new-gripper (Autodesk Fusion 360 design; units mm, degrees)
Autodesk Fusion 360 part; units mm, degrees
sketch "스케치1" plane through (0, 0, 0) normal (0, 0, 1) x (1, 0, 0)
  line L0 (0, 0) -> (40, 0)
  line L1 (40, 0) -> (40, 100)
  line L2 (40, 100) -> (0, 100)
  line L3 (0, 100) -> (0, 0)
  line L4 (50, 0) -> (90, 0)
  line L5 (90, 0) -> (90, 100)
  line L6 (90, 100) -> (50, 100)
  line L7 (50, 100) -> (50, 0)
  dimension "d1" = 40
  dimension "d2" = 100
  dimension "d3" = 40
  dimension "d4" = 100
  constraint horizontal L0
  constraint vertical L1
  constraint horizontal L2
  constraint vertical L3
  constraint coincident L0.start L3.end
  constraint horizontal L4
  constraint vertical L5
  constraint horizontal L6
  constraint vertical L7
  measures "d1" distance of L0.start L0.end
  measures "d2" distance of L0.start L2.end
  measures "d3" distance of L4.start L4.end
  measures "d4" distance of L4.start L6.end
extrude "돌출1" add sketch "스케치1" along normal blind 1.5 contours L0 L1 L2 L3 makes body 1 in component "Component"
extrude "돌출1'" add sketch "스케치1" along normal blind 1.5 separate body contours L4 L5 L6 L7 makes body 2 in component "Component'"
extrude "돌출2" add 1 faces at (90, 33.3333, 0.5) along direction (1, 0, 0) blind 3 on bodies 2 bodies 2 in component "Component'"
extrude "돌출2'" add 1 faces at (0, 66.6667, 0.5) along direction (-1, 0, 0) blind 3 on bodies 1 bodies 1 in component "Component"
sketch "스케치2" plane through (0, 0, 1.5) normal (0, 0, 1) x (-1, 0, 0)
  line L0 (-50, -100) -> (-50, 0)
  line L1 (-50, 0) -> (-93, 0)
  line L2 (-93, 0) -> (-93, -100)
  line L3 (-93, -100) -> (-50, -100)
  line L4 (-93, 0) -> (-90, 0)
  line L5 (-90, 0) -> (-90, -100)
  line L6 (-90, -100) -> (-93, -100)
  line L7 (-93, -100) -> (-93, 0)
  dimension "d13" = 3
  constraint horizontal L4
  constraint vertical L5
  constraint horizontal L6
  constraint vertical L7
  constraint coincident L3 L5.end
  constraint coincident L1.end L2.start
  measures "d13" distance of L1.end L4.end
extrude "돌출1''" add sketch "스케치2" along normal blind 80 separate body contours L1 L2 L3 L4 L5 L6 L7 makes body 3 in component "Component''"
sketch "스케치3" plane through (0, 0, 1.5) normal (0, 0, 1) x (-1, 0, 0)
  line L0 (3, 0) -> (-40, 0)
  line L1 (-40, 0) -> (-40, -100)
  line L2 (-40, -100) -> (3, -100)
  line L3 (3, -100) -> (3, 0)
  line L4 (3, 0) -> (0, 0)
  line L5 (0, 0) -> (0, -100)
  line L6 (0, -100) -> (3, -100)
  line L7 (3, -100) -> (3, 0)
  dimension "d16" = 3
  dimension "d17" = 100
  constraint horizontal L4
  constraint vertical L5
  constraint horizontal L6
  constraint vertical L7
  constraint coincident L0.start L3.end
  measures "d16" distance of L0.start L4.end
  measures "d17" distance of L0.start L2.end
extrude "돌출1'''" add sketch "스케치3" along normal blind 80 separate body contours L0 L2 L3 L4 L5 L6 L7 makes body 4 in component "Component'''"
sketch "스케치4" plane through (0, 0, 81.5) normal (0, 0, 1) x (-1, 0, 0)
  line L0 (3, -100) -> (3, 0)
  line L1 (3, 0) -> (0, 0)
  line L2 (0, 0) -> (0, -100)
  line L3 (0, -100) -> (3, -100)
  line L4 (3, -100) -> (-40, -100)
  line L5 (-40, -100) -> (-40, 0)
  line L6 (-40, 0) -> (3, 0)
  line L7 (3, 0) -> (3, -100)
  dimension "d20" = 43
  dimension "d21" = 100
  constraint horizontal L4
  constraint vertical L5
  constraint horizontal L6
  constraint vertical L7
  constraint coincident L0.start L3.end
  measures "d20" distance of L0.start L4.end
  measures "d21" distance of L0.start L0.end
extrude "돌출1''''" add sketch "스케치4" along normal blind 3 separate body makes body 5 in component "Component''''"
sketch "스케치5" plane through (0, 0, 81.5) normal (0, 0, 1) x (-1, 0, 0)
  line L0 (-93, -100) -> (-90, -100)
  line L1 (-90, -100) -> (-90, 0)
  line L2 (-90, 0) -> (-93, 0)
  line L3 (-93, 0) -> (-93, -100)
  line L4 (-93, -100) -> (-50, -100)
  line L5 (-50, -100) -> (-50, 0)
  line L6 (-50, 0) -> (-93, 0)
  line L7 (-93, 0) -> (-93, -100)
  dimension "d24" = 43
  dimension "d25" = 100
  constraint horizontal L4
  constraint vertical L5
  constraint horizontal L6
  constraint vertical L7
  constraint coincident L0.start L3.end
  measures "d24" distance of L0.start L4.end
  measures "d25" distance of L0.start L2.end
extrude "돌출1'''''" add sketch "스케치5" along normal blind 3 separate body makes body 6 in component "Component'''''"
sketch "스케치6" plane through (0, 0, 84.5) normal (0, 0, 1) x (-1, 0, 0)
  line L0 (-93, 0) -> (-93, -100)
  line L1 (-93, -100) -> (-50, -100)
  line L2 (-50, -100) -> (-50, 0)
  line L3 (-50, 0) -> (-93, 0)
  circle A0 centre (-85, -50) radius 1.5
  dimension "d28" = 3
  dimension "d29" = 35
  dimension "d30" = 50
  measures "d28" diameter of A0
  measures "d29" distance of L2 A0.centre
  measures "d30" distance of L3 A0.centre
sketch "스케치7" plane through (0, 0, 84.5) normal (0, 0, 1) x (-1, 0, 0)
  line L0 (3, 0) -> (-40, 0)
  line L1 (-40, 0) -> (-40, -100)
  line L2 (-40, -100) -> (3, -100)
  line L3 (3, -100) -> (3, 0)
  circle A0 centre (-5, -50) radius 1.5
  dimension "d31" = 3
  dimension "d32" = 35
  measures "d31" diameter of A0
  measures "d32" distance of L1 A0.centre
extrude "돌출2''" cut sketch "스케치7" sketch "스케치6" against normal blind 4 contours A0 of sketch 2 contours A0 bodies 5 in component "Component''''"
extrude "돌출2'''" cut sketch "스케치7" sketch "스케치6" against normal blind 4 contours A0 of sketch 2 contours A0 bodies 6 in component "Component'''''"
sketch "스케치8" plane through (0, 0, 84.5) normal (0, 0, 1) x (-1, 0, 0)
  circle A0 centre (-85, -50) radius 1.5
  line L0 (-93, 0) -> (-93, -100)
  line L1 (-93, -100) -> (-50, -100)
  line L2 (-50, -100) -> (-50, 0)
  line L3 (-50, 0) -> (-93, 0)
  line L4 (-90, -45) -> (-55, -45)
  line L5 (-55, -45) -> (-55, -55)
  line L6 (-55, -55) -> (-90, -55)
  line L7 (-90, -55) -> (-90, -45)
  dimension "d37" = 35
  dimension "d38" = 10
  constraint horizontal L4
  constraint vertical L5
  constraint horizontal L6
  constraint vertical L7
  measures "d37" distance of L4.start L4.end
  measures "d38" distance of L4.start L6.end
extrude "돌출1''''''" add sketch "스케치8" along normal blind 3 separate body contours L4 L5 L6 L7 makes body 7 in component "Component''''''"
sketch "스케치9" plane through (0, 0, 84.5) normal (0, 0, 1) x (-1, 0, 0)
  circle A0 centre (-5, -50) radius 1.5
  line L0 (3, 0) -> (-40, 0)
  line L1 (-40, 0) -> (-40, -100)
  line L2 (-40, -100) -> (3, -100)
  line L3 (3, -100) -> (3, 0)
  line L4 (0, -55) -> (-35, -55)
  line L5 (-35, -55) -> (-35, -45)
  line L6 (-35, -45) -> (0, -45)
  line L7 (0, -45) -> (0, -55)
  dimension "d41" = 35
  dimension "d42" = 10
  constraint horizontal L4
  constraint vertical L5
  constraint horizontal L6
  constraint vertical L7
  measures "d41" distance of L4.start L4.end
  measures "d42" distance of L4.start L6.end
extrude "돌출1'''''''" add sketch "스케치9" along normal blind 3 separate body contours L4 L5 L6 L7 makes body 8 in component "Component'''''''"
sketch "스케치10" plane through (0, 0, 87.5) normal (0, 0, 1) x (-1, 0, 0)
  circle A0 centre (-85, -50) radius 1.5
  line L0 (-90, -55) -> (-55, -55)
  line L1 (-55, -55) -> (-55, -45)
  line L2 (-55, -45) -> (-90, -45)
  line L3 (-90, -45) -> (-90, -55)
  circle A1 centre (-45, -50) radius 25
  circle A2 centre (-60, -50) radius 1.5
  circle A3 centre (-30, -50) radius 1.5
  dimension "d45" = 50
  dimension "d46" = 3
  dimension "d47" = 3
  measures "d45" diameter of A1
  measures "d46" diameter of A2
  measures "d47" diameter of A3
extrude "돌출1''''''''" add sketch "스케치10" along normal blind 10 separate body contours L0 L1 L2 A1 | L0 L1 L2 A1 makes body 9 in component "Component''''''''"
extrude "돌출2''''" cut sketch "스케치10" against normal blind 3 contours A2 | A3 bodies 7 in component "Component''''''"
extrude "돌출2'''''" cut sketch "스케치10" against normal blind 3 contours A2 | A3 bodies 8 in component "Component'''''''"
sketch "스케치11" plane through (0, 0, 84.5) normal (0, 0, 1) x (-1, 0, 0)
  circle A0 centre (-5, -50) radius 1.5
  line L0 (3, 0) -> (-40, 0)
  line L1 (-40, 0) -> (-40, -100)
  line L2 (-40, -100) -> (3, -100)
  line L3 (3, -100) -> (3, 0)
  line L4 (-5, -95) -> (-15, -95)
  line L5 (-15, -95) -> (-15, -85)
  line L6 (-15, -85) -> (-5, -85)
  line L7 (-5, -85) -> (-5, -95)
  line L8 (-5, -5) -> (-15, -5)
  line L9 (-15, -5) -> (-15, -15)
  line L10 (-15, -15) -> (-5, -15)
  line L11 (-5, -15) -> (-5, -5)
  constraint horizontal L4
  constraint vertical L5
  constraint horizontal L6
  constraint vertical L7
  constraint horizontal L8
  constraint vertical L9
  constraint horizontal L10
  constraint vertical L11
sketch "스케치12" plane through (0, 0, 94.5) normal (0, 0, 1) x (-1, 0, 0)
  line L0 (-5, -85) -> (-15, -85)
  line L1 (-15, -85) -> (-15, -95)
  line L2 (-15, -95) -> (-5, -95)
  line L3 (-5, -95) -> (-5, -85)
  line L4 (-15, -85) -> (-10, -85)
  line L5 (-10, -85) -> (-10, -95)
  line L6 (-10, -95) -> (-15, -95)
  line L7 (-15, -95) -> (-15, -85)
  constraint horizontal L4
  constraint vertical L5
  constraint horizontal L6
  constraint vertical L7
  constraint midpoint L2 L5.end
  constraint coincident L0.end L1.start
sketch "스케치13" plane through (0, 0, 87.5) normal (0, 0, 1) x (-1, 0, 0)
  line L0 (-15, -95) -> (-10, -95)
  line L1 (-10, -95) -> (-10, -85)
  line L2 (-10, -85) -> (-15, -85)
  line L3 (-15, -85) -> (-15, -95)
  circle A0 centre (-12.5, -87.5) radius 1.55
  circle A1 centre (-12.5, -92.5) radius 1.55
  dimension "d60" = 3.1
  dimension "d61" = 3.1
  dimension "d62" = 2.5
  dimension "d63" = 2.5
  dimension "d64" = 2.5
  dimension "d65" = 2.5
  measures "d60" diameter of A0
  measures "d61" diameter of A1
  measures "d62" distance of L0 A1.centre
  measures "d63" distance of L1 A1.centre
  measures "d64" distance of L2 A0.centre
  measures "d65" distance of L1 A0.centre
sketch "스케치14" plane through (10, 0, 0) normal (1, 0, 0) x (0, 1, 0)
  line L0 (85, 104.5) -> (85, 87.5)
  line L1 (85, 87.5) -> (95, 87.5)
  line L2 (95, 87.5) -> (95, 104.5)
  line L3 (95, 104.5) -> (85, 104.5)
  line L4 (85, 104.5) -> (95, 104.5)
  line L5 (95, 104.5) -> (95, 96.5)
  line L6 (95, 96.5) -> (85, 96.5)
  line L7 (85, 96.5) -> (85, 104.5)
  line L8 (87.5, 102) -> (92.5, 102)
  line L9 (92.5, 102) -> (92.5, 99)
  line L10 (92.5, 99) -> (87.5, 99)
  line L11 (87.5, 99) -> (87.5, 102)
  dimension "d68" = 8
  dimension "d69" = 5
  dimension "d70" = 3
  dimension "d71" = 2.5
  dimension "d72" = 2.5
  constraint horizontal L4
  constraint vertical L5
  constraint horizontal L6
  constraint vertical L7
  constraint coincident L0.start L3.end
  constraint horizontal L8
  constraint vertical L9
  constraint horizontal L10
  constraint vertical L11
  measures "d68" distance of L0.start L6.end
  measures "d69" distance of L8.start L8.end
  measures "d70" distance of L8.start L10.end
  measures "d71" distance of L7 L11
  measures "d72" distance of L4 L8
extrude "돌출2''''''" cut 1 faces at (45.386, 58.8877, 97.5) along direction (0, 0, -1) blind 7 on bodies 9 bodies 9 in component "Component''''''''"
component "Component" placed x (1, 0, 0) y (0, 1, 0) z (0, 0, 1) at (0, 0, 0)
component "Component'" placed x (1, 0, 0) y (0, 1, 0) z (0, 0, 1) at (0, 0, 0)
component "Component''" placed x (1, 0, 0) y (0, 1, 0) z (0, 0, 1) at (0, 0, 0)
component "Component'''" placed x (1, 0, 0) y (0, 1, 0) z (0, 0, 1) at (0, 0, 0)
component "Component''''" placed x (1, 0, 0) y (0, 1, 0) z (0, 0, 1) at (0, 0, 0)
component "Component'''''" placed x (1, 0, 0) y (0, 1, 0) z (0, 0, 1) at (0, 0, 0)
component "Component''''''" placed x (1, 0, 0) y (0, 1, 0) z (0, 0, 1) at (0, 0, 0)
component "Component'''''''" placed x (1, 0, 0) y (0, 1, 0) z (0, 0, 1) at (0, 0, 0)
component "Component''''''''" placed x (1, 0, 0) y (0, 1, 0) z (0, 0, 1) at (0, 0, 0)
